Autodesk Fusion 360 part; units mm, degrees
(part 3 of 5)
sketch "草图2 (2)" plane through (0, 0, -0.03) normal (0, 0, 1) x (1, 0, 0) in component "02_模具外套筒"
  line L0 (34, 0) -> (33.9193, 0.5551)
  line L1 (33.9193, 0.5551) -> (33.6891, 1.1029)
  line L2 (33.6891, 1.1029) -> (33.3425, 1.638)
  line L3 (33.3425, 1.638) -> (32.9293, 2.1583)
  line L4 (32.9293, 2.1583) -> (32.5082, 2.6655)
  line L5 (32.5082, 2.6655) -> (32.1374, 3.1653)
  line L6 (32.1374, 3.1653) -> (31.866, 3.6659)
  line L7 (31.866, 3.6659) -> (31.7262, 4.1768)
  line L8 (31.7262, 4.1768) -> (31.7289, 4.7065)
  line L9 (31.7289, 4.7065) -> (31.8616, 5.2604)
  line L10 (31.8616, 5.2604) -> (32.0904, 5.839)
  line L11 (32.0904, 5.839) -> (32.3659, 6.438)
  line L12 (32.3659, 6.438) -> (32.6303, 7.0475)
  line L13 (32.6303, 7.0475) -> (32.8266, 7.6541)
  line L14 (32.8266, 7.6541) -> (32.9072, 8.2428)
  line L15 (32.9072, 8.2428) -> (32.8415, 8.7998)
  line L16 (32.8415, 8.7998) -> (32.6199, 9.3151)
  line L17 (32.6199, 9.3151) -> (32.2557, 9.7847)
  line L18 (32.2557, 9.7847) -> (31.7824, 10.2119)
  line L19 (31.7824, 10.2119) -> (31.2487, 10.6075)
  line L20 (31.2487, 10.6075) -> (30.7106, 10.9884)
  line L21 (30.7106, 10.9884) -> (30.2231, 11.3752)
  line L22 (30.2231, 11.3752) -> (29.8313, 11.7885)
  line L23 (29.8313, 11.7885) -> (29.5641, 12.2459)
  line L24 (29.5641, 12.2459) -> (29.4297, 12.7582)
  line L25 (29.4297, 12.7582) -> (29.4144, 13.3275)
  line L26 (29.4144, 13.3275) -> (29.4857, 13.9457)
  line L27 (29.4857, 13.9457) -> (29.5968, 14.5955)
  line L28 (29.5968, 14.5955) -> (29.6944, 15.2527)
  line L29 (29.6944, 15.2527) -> (29.727, 15.8894)
  line L30 (29.727, 15.8894) -> (29.6525, 16.479)
  line L31 (29.6525, 16.479) -> (29.4449, 17)
  line L32 (29.4449, 17) -> (29.0975, 17.4404)
  line L33 (29.0975, 17.4404) -> (28.6241, 17.7996)
  line L34 (28.6241, 17.7996) -> (28.0564, 18.0898)
  line L35 (28.0564, 18.0898) -> (27.4385, 18.3338)
  line L36 (27.4385, 18.3338) -> (26.8202, 18.5625)
  line L37 (26.8202, 18.5625) -> (26.2492, 18.8099)
  line L38 (26.2492, 18.8099) -> (25.7638, 19.1077)
  line L39 (25.7638, 19.1077) -> (25.3873, 19.4804)
  line L40 (25.3873, 19.4804) -> (25.1248, 19.9405)
  line L41 (25.1248, 19.9405) -> (24.9627, 20.4864)
  line L42 (24.9627, 20.4864) -> (24.8716, 21.102)
  line L43 (24.8716, 21.102) -> (24.8107, 21.7584)
  line L44 (24.8107, 21.7584) -> (24.7349, 22.4184)
  line L45 (24.7349, 22.4184) -> (24.6016, 23.0419)
  line L46 (24.6016, 23.0419) -> (24.3771, 23.5921)
  line L47 (24.3771, 23.5921) -> (24.0416, 24.0416)
  line L48 (24.0416, 24.0416) -> (23.5921, 24.3771)
  line L49 (23.5921, 24.3771) -> (23.0419, 24.6016)
  line L50 (23.0419, 24.6016) -> (22.4184, 24.7349)
  line L51 (22.4184, 24.7349) -> (21.7584, 24.8107)
  line L52 (21.7584, 24.8107) -> (21.102, 24.8716)
  line L53 (21.102, 24.8716) -> (20.4864, 24.9627)
  line L54 (20.4864, 24.9627) -> (19.9405, 25.1248)
  line L55 (19.9405, 25.1248) -> (19.4804, 25.3873)
  line L56 (19.4804, 25.3873) -> (19.1077, 25.7638)
  line L57 (19.1077, 25.7638) -> (18.8099, 26.2492)
  line L58 (18.8099, 26.2492) -> (18.5625, 26.8202)
  line L59 (18.5625, 26.8202) -> (18.3338, 27.4385)
  line L60 (18.3338, 27.4385) -> (18.0898, 28.0564)
  line L61 (18.0898, 28.0564) -> (17.7996, 28.6241)
  line L62 (17.7996, 28.6241) -> (17.4404, 29.0975)
  line L63 (17.4404, 29.0975) -> (17, 29.4449)
  line L64 (17, 29.4449) -> (16.479, 29.6525)
  line L65 (16.479, 29.6525) -> (15.8894, 29.727)
  line L66 (15.8894, 29.727) -> (15.2527, 29.6944)
  line L67 (15.2527, 29.6944) -> (14.5955, 29.5968)
  line L68 (14.5955, 29.5968) -> (13.9457, 29.4857)
  line L69 (13.9457, 29.4857) -> (13.3275, 29.4144)
  line L70 (13.3275, 29.4144) -> (12.7582, 29.4297)
  line L71 (12.7582, 29.4297) -> (12.2459, 29.5641)
  line L72 (12.2459, 29.5641) -> (11.7885, 29.8313)
  line L73 (11.7885, 29.8313) -> (11.3752, 30.2231)
  line L74 (11.3752, 30.2231) -> (10.9884, 30.7106)
  line L75 (10.9884, 30.7106) -> (10.6075, 31.2487)
  line L76 (10.6075, 31.2487) -> (10.2119, 31.7824)
  line L77 (10.2119, 31.7824) -> (9.7847, 32.2557)
  line L78 (9.7847, 32.2557) -> (9.3151, 32.6199)
  line L79 (9.3151, 32.6199) -> (8.7998, 32.8415)
  line L80 (8.7998, 32.8415) -> (8.2428, 32.9072)
  line L81 (8.2428, 32.9072) -> (7.6541, 32.8266)
  line L82 (7.6541, 32.8266) -> (7.0475, 32.6303)
  line L83 (7.0475, 32.6303) -> (6.438, 32.3659)
  line L84 (6.438, 32.3659) -> (5.839, 32.0904)
  line L85 (5.839, 32.0904) -> (5.2604, 31.8616)
  line L86 (5.2604, 31.8616) -> (4.7065, 31.7289)
  line L87 (4.7065, 31.7289) -> (4.1768, 31.7262)
  line L88 (4.1768, 31.7262) -> (3.6659, 31.866)
  line L89 (3.6659, 31.866) -> (3.1653, 32.1374)
  line L90 (3.1653, 32.1374) -> (2.6655, 32.5082)
  line L91 (2.6655, 32.5082) -> (2.1583, 32.9293)
  line L92 (2.1583, 32.9293) -> (1.638, 33.3425)
  line L93 (1.638, 33.3425) -> (1.1029, 33.6891)
  line L94 (1.1029, 33.6891) -> (0.5551, 33.9193)
  line L95 (0.5551, 33.9193) -> (0, 34)
  line L96 (0, 34) -> (-0.5551, 33.9193)
  line L97 (-0.5551, 33.9193) -> (-1.1029, 33.6891)
  line L98 (-1.1029, 33.6891) -> (-1.638, 33.3425)
  line L99 (-1.638, 33.3425) -> (-2.1583, 32.9293)
  line L100 (-2.1583, 32.9293) -> (-2.6655, 32.5082)
  line L101 (-2.6655, 32.5082) -> (-3.1653, 32.1374)
  line L102 (-3.1653, 32.1374) -> (-3.6659, 31.866)
  line L103 (-3.6659, 31.866) -> (-4.1768, 31.7262)
  line L104 (-4.1768, 31.7262) -> (-4.7065, 31.7289)
  line L105 (-4.7065, 31.7289) -> (-5.2604, 31.8616)
  line L106 (-5.2604, 31.8616) -> (-5.839, 32.0904)
  line L107 (-5.839, 32.0904) -> (-6.438, 32.3659)
  line L108 (-6.438, 32.3659) -> (-7.0475, 32.6303)
  line L109 (-7.0475, 32.6303) -> (-7.6541, 32.8266)
  line L110 (-7.6541, 32.8266) -> (-8.2428, 32.9072)
  line L111 (-8.2428, 32.9072) -> (-8.7998, 32.8415)
  line L112 (-8.7998, 32.8415) -> (-9.3151, 32.6199)
  line L113 (-9.3151, 32.6199) -> (-9.7847, 32.2557)
  line L114 (-9.7847, 32.2557) -> (-10.2119, 31.7824)
  line L115 (-10.2119, 31.7824) -> (-10.6075, 31.2487)
  line L116 (-10.6075, 31.2487) -> (-10.9884, 30.7106)
  line L117 (-10.9884, 30.7106) -> (-11.3752, 30.2231)
  line L118 (-11.3752, 30.2231) -> (-11.7885, 29.8313)
  line L119 (-11.7885, 29.8313) -> (-12.2459, 29.5641)
  line L120 (-12.2459, 29.5641) -> (-12.7582, 29.4297)
  line L121 (-12.7582, 29.4297) -> (-13.3275, 29.4144)
  line L122 (-13.3275, 29.4144) -> (-13.9457, 29.4857)
  line L123 (-13.9457, 29.4857) -> (-14.5955, 29.5968)
  line L124 (-14.5955, 29.5968) -> (-15.2527, 29.6944)
  line L125 (-15.2527, 29.6944) -> (-15.8894, 29.727)
  line L126 (-15.8894, 29.727) -> (-16.479, 29.6525)
  line L127 (-16.479, 29.6525) -> (-17, 29.4449)
  line L128 (-17, 29.4449) -> (-17.4404, 29.0975)
  line L129 (-17.4404, 29.0975) -> (-17.7996, 28.6241)
  line L130 (-17.7996, 28.6241) -> (-18.0898, 28.0564)
  line L131 (-18.0898, 28.0564) -> (-18.3338, 27.4385)
  line L132 (-18.3338, 27.4385) -> (-18.5625, 26.8202)
  line L133 (-18.5625, 26.8202) -> (-18.8099, 26.2492)
  line L134 (-18.8099, 26.2492) -> (-19.1077, 25.7638)
  line L135 (-19.1077, 25.7638) -> (-19.4804, 25.3873)
  line L136 (-19.4804, 25.3873) -> (-19.9405, 25.1248)
  line L137 (-19.9405, 25.1248) -> (-20.4864, 24.9627)
  line L138 (-20.4864, 24.9627) -> (-21.102, 24.8716)
  line L139 (-21.102, 24.8716) -> (-21.7584, 24.8107)
  line L140 (-21.7584, 24.8107) -> (-22.4184, 24.7349)
  line L141 (-22.4184, 24.7349) -> (-23.0419, 24.6016)
  line L142 (-23.0419, 24.6016) -> (-23.5921, 24.3771)
  line L143 (-23.5921, 24.3771) -> (-24.0416, 24.0416)
  line L144 (-24.0416, 24.0416) -> (-24.3771, 23.5921)
  line L145 (-24.3771, 23.5921) -> (-24.6016, 23.0419)
  line L146 (-24.6016, 23.0419) -> (-24.7349, 22.4184)
  line L147 (-24.7349, 22.4184) -> (-24.8107, 21.7584)
  line L148 (-24.8107, 21.7584) -> (-24.8716, 21.102)
  line L149 (-24.8716, 21.102) -> (-24.9627, 20.4864)
  line L150 (-24.9627, 20.4864) -> (-25.1248, 19.9405)
  line L151 (-25.1248, 19.9405) -> (-25.3873, 19.4804)
  line L152 (-25.3873, 19.4804) -> (-25.7638, 19.1077)
  line L153 (-25.7638, 19.1077) -> (-26.2492, 18.8099)
  line L154 (-26.2492, 18.8099) -> (-26.8202, 18.5625)
  line L155 (-26.8202, 18.5625) -> (-27.4385, 18.3338)
  line L156 (-27.4385, 18.3338) -> (-28.0564, 18.0898)
  line L157 (-28.0564, 18.0898) -> (-28.6241, 17.7996)
  line L158 (-28.6241, 17.7996) -> (-29.0975, 17.4404)
  line L159 (-29.0975, 17.4404) -> (-29.4449, 17)
  line L160 (-29.4449, 17) -> (-29.6525, 16.479)
  line L161 (-29.6525, 16.479) -> (-29.727, 15.8894)
  line L162 (-29.727, 15.8894) -> (-29.6944, 15.2527)
  line L163 (-29.6944, 15.2527) -> (-29.5968, 14.5955)
  line L164 (-29.5968, 14.5955) -> (-29.4857, 13.9457)
  line L165 (-29.4857, 13.9457) -> (-29.4144, 13.3275)
  line L166 (-29.4144, 13.3275) -> (-29.4297, 12.7582)
  line L167 (-29.4297, 12.7582) -> (-29.5641, 12.2459)
  line L168 (-29.5641, 12.2459) -> (-29.8313, 11.7885)
  line L169 (-29.8313, 11.7885) -> (-30.2231, 11.3752)
  line L170 (-30.2231, 11.3752) -> (-30.7106, 10.9884)
  line L171 (-30.7106, 10.9884) -> (-31.2487, 10.6075)
  line L172 (-31.2487, 10.6075) -> (-31.7824, 10.2119)
  line L173 (-31.7824, 10.2119) -> (-32.2557, 9.7847)
  line L174 (-32.2557, 9.7847) -> (-32.6199, 9.3151)
  line L175 (-32.6199, 9.3151) -> (-32.8415, 8.7998)
  line L176 (-32.8415, 8.7998) -> (-32.9072, 8.2428)
  line L177 (-32.9072, 8.2428) -> (-32.8266, 7.6541)
  line L178 (-32.8266, 7.6541) -> (-32.6303, 7.0475)
  line L179 (-32.6303, 7.0475) -> (-32.3659, 6.438)
  line L180 (-32.3659, 6.438) -> (-32.0904, 5.839)
  line L181 (-32.0904, 5.839) -> (-31.8616, 5.2604)
  line L182 (-31.8616, 5.2604) -> (-31.7289, 4.7065)
  line L183 (-31.7289, 4.7065) -> (-31.7262, 4.1768)
  line L184 (-31.7262, 4.1768) -> (-31.866, 3.6659)
  line L185 (-31.866, 3.6659) -> (-32.1374, 3.1653)
  line L186 (-32.1374, 3.1653) -> (-32.5082, 2.6655)
  line L187 (-32.5082, 2.6655) -> (-32.9293, 2.1583)
  line L188 (-32.9293, 2.1583) -> (-33.3425, 1.638)
  line L189 (-33.3425, 1.638) -> (-33.6891, 1.1029)
  line L190 (-33.6891, 1.1029) -> (-33.9193, 0.5551)
  line L191 (-33.9193, 0.5551) -> (-34, 0)
  line L192 (-34, 0) -> (-33.9193, -0.5551)
  line L193 (-33.9193, -0.5551) -> (-33.6891, -1.1029)
  line L194 (-33.6891, -1.1029) -> (-33.3425, -1.638)
  line L195 (-33.3425, -1.638) -> (-32.9293, -2.1583)
  line L196 (-32.9293, -2.1583) -> (-32.5082, -2.6655)
  line L197 (-32.5082, -2.6655) -> (-32.1374, -3.1653)
  line L198 (-32.1374, -3.1653) -> (-31.866, -3.6659)
  line L199 (-31.866, -3.6659) -> (-31.7262, -4.1768)
  line L200 (-31.7262, -4.1768) -> (-31.7289, -4.7065)
  line L201 (-31.7289, -4.7065) -> (-31.8616, -5.2604)
  line L202 (-31.8616, -5.2604) -> (-32.0904, -5.839)
  line L203 (-32.0904, -5.839) -> (-32.3659, -6.438)
  line L204 (-32.3659, -6.438) -> (-32.6303, -7.0475)
  line L205 (-32.6303, -7.0475) -> (-32.8266, -7.6541)
  line L206 (-32.8266, -7.6541) -> (-32.9072, -8.2428)
  line L207 (-32.9072, -8.2428) -> (-32.8415, -8.7998)
  line L208 (-32.8415, -8.7998) -> (-32.6199, -9.3151)
  line L209 (-32.6199, -9.3151) -> (-32.2557, -9.7847)
  line L210 (-32.2557, -9.7847) -> (-31.7824, -10.2119)
  line L211 (-31.7824, -10.2119) -> (-31.2487, -10.6075)
  line L212 (-31.2487, -10.6075) -> (-30.7106, -10.9884)
  line L213 (-30.7106, -10.9884) -> (-30.2231, -11.3752)
  line L214 (-30.2231, -11.3752) -> (-29.8313, -11.7885)
  line L215 (-29.8313, -11.7885) -> (-29.5641, -12.2459)
  line L216 (-29.5641, -12.2459) -> (-29.4297, -12.7582)
  line L217 (-29.4297, -12.7582) -> (-29.4144, -13.3275)
  line L218 (-29.4144, -13.3275) -> (-29.4857, -13.9457)
  line L219 (-29.4857, -13.9457) -> (-29.5968, -14.5955)
  line L220 (-29.5968, -14.5955) -> (-29.6944, -15.2527)
  line L221 (-29.6944, -15.2527) -> (-29.727, -15.8894)
  line L222 (-29.727, -15.8894) -> (-29.6525, -16.479)
  line L223 (-29.6525, -16.479) -> (-29.4449, -17)
  line L224 (-29.4449, -17) -> (-29.0975, -17.4404)
  line L225 (-29.0975, -17.4404) -> (-28.6241, -17.7996)
  line L226 (-28.6241, -17.7996) -> (-28.0564, -18.0898)
  line L227 (-28.0564, -18.0898) -> (-27.4385, -18.3338)
  line L228 (-27.4385, -18.3338) -> (-26.8202, -18.5625)
  line L229 (-26.8202, -18.5625) -> (-26.2492, -18.8099)
  line L230 (-26.2492, -18.8099) -> (-25.7638, -19.1077)
  line L231 (-25.7638, -19.1077) -> (-25.3873, -19.4804)
  line L232 (-25.3873, -19.4804) -> (-25.1248, -19.9405)
  line L233 (-25.1248, -19.9405) -> (-24.9627, -20.4864)
  line L234 (-24.9627, -20.4864) -> (-24.8716, -21.102)
  line L235 (-24.8716, -21.102) -> (-24.8107, -21.7584)
  line L236 (-24.8107, -21.7584) -> (-24.7349, -22.4184)
  line L237 (-24.7349, -22.4184) -> (-24.6016, -23.0419)
  line L238 (-24.6016, -23.0419) -> (-24.3771, -23.5921)
  line L239 (-24.3771, -23.5921) -> (-24.0416, -24.0416)
  line L240 (-24.0416, -24.0416) -> (-23.5921, -24.3771)
  line L241 (-23.5921, -24.3771) -> (-23.0419, -24.6016)
  line L242 (-23.0419, -24.6016) -> (-22.4184, -24.7349)
  line L243 (-22.4184, -24.7349) -> (-21.7584, -24.8107)
  line L244 (-21.7584, -24.8107) -> (-21.102, -24.8716)
  line L245 (-21.102, -24.8716) -> (-20.4864, -24.9627)
  line L246 (-20.4864, -24.9627) -> (-19.9405, -25.1248)
  line L247 (-19.9405, -25.1248) -> (-19.4804, -25.3873)
  line L248 (-19.4804, -25.3873) -> (-19.1077, -25.7638)
  line L249 (-19.1077, -25.7638) -> (-18.8099, -26.2492)
  line L250 (-18.8099, -26.2492) -> (-18.5625, -26.8202)
  line L251 (-18.5625, -26.8202) -> (-18.3338, -27.4385)
  line L252 (-18.3338, -27.4385) -> (-18.0898, -28.0564)
  line L253 (-18.0898, -28.0564) -> (-17.7996, -28.6241)
  line L254 (-17.7996, -28.6241) -> (-17.4404, -29.0975)
  line L255 (-17.4404, -29.0975) -> (-17, -29.4449)
  line L256 (-17, -29.4449) -> (-16.479, -29.6525)
  line L257 (-16.479, -29.6525) -> (-15.8894, -29.727)
  line L258 (-15.8894, -29.727) -> (-15.2527, -29.6944)
  line L259 (-15.2527, -29.6944) -> (-14.5955, -29.5968)
  line L260 (-14.5955, -29.5968) -> (-13.9457, -29.4857)
  line L261 (-13.9457, -29.4857) -> (-13.3275, -29.4144)
  line L262 (-13.3275, -29.4144) -> (-12.7582, -29.4297)
  line L263 (-12.7582, -29.4297) -> (-12.2459, -29.5641)
  line L264 (-12.2459, -29.5641) -> (-11.7885, -29.8313)
  line L265 (-11.7885, -29.8313) -> (-11.3752, -30.2231)
  line L266 (-11.3752, -30.2231) -> (-10.9884, -30.7106)
  line L267 (-10.9884, -30.7106) -> (-10.6075, -31.2487)
  line L268 (-10.6075, -31.2487) -> (-10.2119, -31.7824)
  line L269 (-10.2119, -31.7824) -> (-9.7847, -32.2557)
  line L270 (-9.7847, -32.2557) -> (-9.3151, -32.6199)
  line L271 (-9.3151, -32.6199) -> (-8.7998, -32.8415)
  line L272 (-8.7998, -32.8415) -> (-8.2428, -32.9072)
  line L273 (-8.2428, -32.9072) -> (-7.6541, -32.8266)
  line L274 (-7.6541, -32.8266) -> (-7.0475, -32.6303)
  line L275 (-7.0475, -32.6303) -> (-6.438, -32.3659)
  line L276 (-6.438, -32.3659) -> (-5.839, -32.0904)
  line L277 (-5.839, -32.0904) -> (-5.2604, -31.8616)
  line L278 (-5.2604, -31.8616) -> (-4.7065, -31.7289)
  line L279 (-4.7065, -31.7289) -> (-4.1768, -31.7262)
  line L280 (-4.1768, -31.7262) -> (-3.6659, -31.866)
  line L281 (-3.6659, -31.866) -> (-3.1653, -32.1374)
  line L282 (-3.1653, -32.1374) -> (-2.6655, -32.5082)
  line L283 (-2.6655, -32.5082) -> (-2.1583, -32.9293)
  line L284 (-2.1583, -32.9293) -> (-1.638, -33.3425)
  line L285 (-1.638, -33.3425) -> (-1.1029, -33.6891)
  line L286 (-1.1029, -33.6891) -> (-0.5551, -33.9193)
  line L287 (-0.5551, -33.9193) -> (0, -34)
  line L288 (0, -34) -> (0.5551, -33.9193)
  line L289 (0.5551, -33.9193) -> (1.1029, -33.6891)
  line L290 (1.1029, -33.6891) -> (1.638, -33.3425)
  line L291 (1.638, -33.3425) -> (2.1583, -32.9293)
  line L292 (2.1583, -32.9293) -> (2.6655, -32.5082)
  line L293 (2.6655, -32.5082) -> (3.1653, -32.1374)
  line L294 (3.1653, -32.1374) -> (3.6659, -31.866)
  line L295 (3.6659, -31.866) -> (4.1768, -31.7262)
  line L296 (4.1768, -31.7262) -> (4.7065, -31.7289)
  line L297 (4.7065, -31.7289) -> (5.2604, -31.8616)
  line L298 (5.2604, -31.8616) -> (5.839, -32.0904)
  line L299 (5.839, -32.0904) -> (6.438, -32.3659)
  line L300 (6.438, -32.3659) -> (7.0475, -32.6303)
  line L301 (7.0475, -32.6303) -> (7.6541, -32.8266)
  line L302 (7.6541, -32.8266) -> (8.2428, -32.9072)
  line L303 (8.2428, -32.9072) -> (8.7998, -32.8415)
  line L304 (8.7998, -32.8415) -> (9.3151, -32.6199)
  line L305 (9.3151, -32.6199) -> (9.7847, -32.2557)
  line L306 (9.7847, -32.2557) -> (10.2119, -31.7824)
  line L307 (10.2119, -31.7824) -> (10.6075, -31.2487)
  line L308 (10.6075, -31.2487) -> (10.9884, -30.7106)
  line L309 (10.9884, -30.7106) -> (11.3752, -30.2231)
  line L310 (11.3752, -30.2231) -> (11.7885, -29.8313)
  line L311 (11.7885, -29.8313) -> (12.2459, -29.5641)
  line L312 (12.2459, -29.5641) -> (12.7582, -29.4297)
  line L313 (12.7582, -29.4297) -> (13.3275, -29.4144)
  line L314 (13.3275, -29.4144) -> (13.9457, -29.4857)
  line L315 (13.9457, -29.4857) -> (14.5955, -29.5968)
  line L316 (14.5955, -29.5968) -> (15.2527, -29.6944)
  line L317 (15.2527, -29.6944) -> (15.8894, -29.727)
  line L318 (15.8894, -29.727) -> (16.479, -29.6525)
  line L319 (16.479, -29.6525) -> (17, -29.4449)
  line L320 (17, -29.4449) -> (17.4404, -29.0975)
  line L321 (17.4404, -29.0975) -> (17.7996, -28.6241)
  line L322 (17.7996, -28.6241) -> (18.0898, -28.0564)
  line L323 (18.0898, -28.0564) -> (18.3338, -27.4385)
  line L324 (18.3338, -27.4385) -> (18.5625, -26.8202)
  line L325 (18.5625, -26.8202) -> (18.8099, -26.2492)
  line L326 (18.8099, -26.2492) -> (19.1077, -25.7638)
  line L327 (19.1077, -25.7638) -> (19.4804, -25.3873)
  line L328 (19.4804, -25.3873) -> (19.9405, -25.1248)
  line L329 (19.9405, -25.1248) -> (20.4864, -24.9627)
  line L330 (20.4864, -24.9627) -> (21.102, -24.8716)
  line L331 (21.102, -24.8716) -> (21.7584, -24.8107)
  line L332 (21.7584, -24.8107) -> (22.4184, -24.7349)
  line L333 (22.4184, -24.7349) -> (23.0419, -24.6016)
  line L334 (23.0419, -24.6016) -> (23.5921, -24.3771)
  line L335 (23.5921, -24.3771) -> (24.0416, -24.0416)
  line L336 (24.0416, -24.0416) -> (24.3771, -23.5921)
  line L337 (24.3771, -23.5921) -> (24.6016, -23.0419)
  line L338 (24.6016, -23.0419) -> (24.7349, -22.4184)
  line L339 (24.7349, -22.4184) -> (24.8107, -21.7584)
  line L340 (24.8107, -21.7584) -> (24.8716, -21.102)
  line L341 (24.8716, -21.102) -> (24.9627, -20.4864)
  line L342 (24.9627, -20.4864) -> (25.1248, -19.9405)
  line L343 (25.1248, -19.9405) -> (25.3873, -19.4804)
  line L344 (25.3873, -19.4804) -> (25.7638, -19.1077)
  line L345 (25.7638, -19.1077) -> (26.2492, -18.8099)
  line L346 (26.2492, -18.8099) -> (26.8202, -18.5625)
  line L347 (26.8202, -18.5625) -> (27.4385, -18.3338)
  line L348 (27.4385, -18.3338) -> (28.0564, -18.0898)
  line L349 (28.0564, -18.0898) -> (28.6241, -17.7996)
  line L350 (28.6241, -17.7996) -> (29.0975, -17.4404)
  line L351 (29.0975, -17.4404) -> (29.4449, -17)
  line L352 (29.4449, -17) -> (29.6525, -16.479)
  line L353 (29.6525, -16.479) -> (29.727, -15.8894)
  line L354 (29.727, -15.8894) -> (29.6944, -15.2527)
  line L355 (29.6944, -15.2527) -> (29.5968, -14.5955)
  line L356 (29.5968, -14.5955) -> (29.4857, -13.9457)
  line L357 (29.4857, -13.9457) -> (29.4144, -13.3275)
  line L358 (29.4144, -13.3275) -> (29.4297, -12.7582)
  line L359 (29.4297, -12.7582) -> (29.5641, -12.2459)
  line L360 (29.5641, -12.2459) -> (29.8313, -11.7885)
  line L361 (29.8313, -11.7885) -> (30.2231, -11.3752)
  line L362 (30.2231, -11.3752) -> (30.7106, -10.9884)
  line L363 (30.7106, -10.9884) -> (31.2487, -10.6075)
  line L364 (31.2487, -10.6075) -> (31.7824, -10.2119)
  line L365 (31.7824, -10.2119) -> (32.2557, -9.7847)
  line L366 (32.2557, -9.7847) -> (32.6199, -9.3151)
  line L367 (32.6199, -9.3151) -> (32.8415, -8.7998)
  line L368 (32.8415, -8.7998) -> (32.9072, -8.2428)
  line L369 (32.9072, -8.2428) -> (32.8266, -7.6541)
  line L370 (32.8266, -7.6541) -> (32.6303, -7.0475)
  line L371 (32.6303, -7.0475) -> (32.3659, -6.438)
  line L372 (32.3659, -6.438) -> (32.0904, -5.839)
  line L373 (32.0904, -5.839) -> (31.8616, -5.2604)
  line L374 (31.8616, -5.2604) -> (31.7289, -4.7065)
  line L375 (31.7289, -4.7065) -> (31.7262, -4.1768)
  line L376 (31.7262, -4.1768) -> (31.866, -3.6659)
  line L377 (31.866, -3.6659) -> (32.1374, -3.1653)
  line L378 (32.1374, -3.1653) -> (32.5082, -2.6655)
  line L379 (32.5082, -2.6655) -> (32.9293, -2.1583)
  line L380 (32.9293, -2.1583) -> (33.3425, -1.638)
  line L381 (33.3425, -1.638) -> (33.6891, -1.1029)
  line L382 (33.6891, -1.1029) -> (33.9193, -0.5551)
  line L383 (33.9193, -0.5551) -> (34, 0)
extrude "配合花边内腔 (1)" cut sketch "草图2 (2)" along normal blind 50.06 bodies 2 in component "02_模具外套筒"
ref_plane "工作平面2" through (0, 0, 49.97) normal (0, 0, 1) x (1, 0, 0) in component "02_模具外套筒"
sketch "草图3 (2)" plane through (0, 0, 49.97) normal (0, 0, 1) x (1, 0, 0) in component "02_模具外套筒"
  circle A0 centre (0, 0) radius 37.5
  circle A1 centre (0, 0) radius 6.3
extrude "推杆导向顶盖 (1)" add sketch "草图3 (2)" along normal blind 3.53 bodies 2 in component "02_模具外套筒"
ref_plane "工作平面3" through (0, 0, 42) normal (0, 0, 1) x (1, 0, 0) in component "02_模具外套筒"
sketch "草图4 (2)" plane through (0, 0, 42) normal (0, 0, 1) x (1, 0, 0) in component "02_模具外套筒"
  line L0 (-53.5, -9) -> (-35.5, -9)
  line L1 (-35.5, -9) -> (-35.5, 9)
  line L2 (-35.5, 9) -> (-53.5, 9)
  line L3 (-53.5, 9) -> (-53.5, -9)
extrude "套筒握耳 (1)" add sketch "草图4 (2)" along normal blind 6 bodies 2 in component "02_模具外套筒"
ref_plane "工作平面4" through (0, 0, 42) normal (0, 0, 1) x (1, 0, 0) in component "02_模具外套筒"
sketch "草图5 (2)" plane through (0, 0, 42) normal (0, 0, 1) x (1, 0, 0) in component "02_模具外套筒"
  line L0 (35.5, -9) -> (53.5, -9)
  line L1 (53.5, -9) -> (53.5, 9)
  line L2 (53.5, 9) -> (35.5, 9)
  line L3 (35.5, 9) -> (35.5, -9)
extrude "套筒握耳 (2)" add sketch "草图5 (2)" along normal blind 6 bodies 2 in component "02_模具外套筒"
sketch "草图1 (3)" plane through (0, 0, 0) normal (0, 0, 1) x (1, 0, 0) in component "03_可换镜像凹纹压片"
  line L0 (-33.6193, -0.5502) -> (-33.3893, -1.0931)
  line L1 (-33.3893, -1.0931) -> (-33.0429, -1.6233)
  line L2 (-33.0429, -1.6233) -> (-32.6299, -2.1387)
  line L3 (-32.6299, -2.1387) -> (-32.2092, -2.641)
  line L4 (-32.2092, -2.641) -> (-31.8388, -3.1359)
  line L5 (-31.8388, -3.1359) -> (-31.568, -3.6316)
  line L6 (-31.568, -3.6316) -> (-31.4288, -4.1376)
  line L7 (-31.4288, -4.1376) -> (-31.4321, -4.6625)
  line L8 (-31.4321, -4.6625) -> (-31.5656, -5.2115)
  line L9 (-31.5656, -5.2115) -> (-31.7952, -5.7853)
  line L10 (-31.7952, -5.7853) -> (-32.0717, -6.3795)
  line L11 (-32.0717, -6.3795) -> (-32.3371, -6.9842)
  line L12 (-32.3371, -6.9842) -> (-32.5344, -7.586)
  line L13 (-32.5344, -7.586) -> (-32.6162, -8.1699)
  line L14 (-32.6162, -8.1699) -> (-32.5517, -8.7222)
  line L15 (-32.5517, -8.7222) -> (-32.3314, -9.2327)
  line L16 (-32.3314, -9.2327) -> (-31.9686, -9.6976)
  line L17 (-31.9686, -9.6976) -> (-31.4968, -10.1201)
  line L18 (-31.4968, -10.1201) -> (-30.9646, -10.5111)
  line L19 (-30.9646, -10.5111) -> (-30.4281, -10.8873)
  line L20 (-30.4281, -10.8873) -> (-29.9423, -11.2695)
  line L21 (-29.9423, -11.2695) -> (-29.5523, -11.6782)
  line L22 (-29.5523, -11.6782) -> (-29.2869, -12.1311)
  line L23 (-29.2869, -12.1311) -> (-29.1545, -12.6389)
  line L24 (-29.1545, -12.6389) -> (-29.1411, -13.2037)
  line L25 (-29.1411, -13.2037) -> (-29.2145, -13.8174)
  line L26 (-29.2145, -13.8174) -> (-29.3277, -14.4628)
  line L27 (-29.3277, -14.4628) -> (-29.4275, -15.1156)
  line L28 (-29.4275, -15.1156) -> (-29.4624, -15.748)
  line L29 (-29.4624, -15.748) -> (-29.3903, -16.3333)
  line L30 (-29.3903, -16.3333) -> (-29.1851, -16.85)
  line L31 (-29.1851, -16.85) -> (-28.8402, -17.2862)
  line L32 (-28.8402, -17.2862) -> (-28.3693, -17.6412)
  line L33 (-28.3693, -17.6412) -> (-27.8043, -17.9272)
  line L34 (-27.8043, -17.9272) -> (-27.1891, -18.1671)
  line L35 (-27.1891, -18.1671) -> (-26.5735, -18.3918)
  line L36 (-26.5735, -18.3918) -> (-26.0053, -18.6352)
  line L37 (-26.0053, -18.6352) -> (-25.5228, -18.929)
  line L38 (-25.5228, -18.929) -> (-25.1493, -19.2978)
  line L39 (-25.1493, -19.2978) -> (-24.8898, -19.754)
  line L40 (-24.8898, -19.754) -> (-24.7308, -20.2961)
  line L41 (-24.7308, -20.2961) -> (-24.6428, -20.9079)
  line L42 (-24.6428, -20.9079) -> (-24.5851, -21.5606)
  line L43 (-24.5851, -21.5606) -> (-24.5126, -22.2169)
  line L44 (-24.5126, -22.2169) -> (-24.3826, -22.8368)
  line L45 (-24.3826, -22.8368) -> (-24.1615, -23.3835)
  line L46 (-24.1615, -23.3835) -> (-23.8295, -23.8295)
  line L47 (-23.8295, -23.8295) -> (-23.3835, -24.1615)
  line L48 (-23.3835, -24.1615) -> (-22.8368, -24.3826)
  line L49 (-22.8368, -24.3826) -> (-22.2169, -24.5126)
  line L50 (-22.2169, -24.5126) -> (-21.5606, -24.5851)
  line L51 (-21.5606, -24.5851) -> (-20.9079, -24.6428)
  line L52 (-20.9079, -24.6428) -> (-20.2961, -24.7308)
  line L53 (-20.2961, -24.7308) -> (-19.754, -24.8898)
  line L54 (-19.754, -24.8898) -> (-19.2978, -25.1493)
  line L55 (-19.2978, -25.1493) -> (-18.929, -25.5228)
  line L56 (-18.929, -25.5228) -> (-18.6352, -26.0053)
  line L57 (-18.6352, -26.0053) -> (-18.3918, -26.5735)
  line L58 (-18.3918, -26.5735) -> (-18.1671, -27.1891)
  line L59 (-18.1671, -27.1891) -> (-17.9272, -27.8043)
  line L60 (-17.9272, -27.8043) -> (-17.6412, -28.3693)
  line L61 (-17.6412, -28.3693) -> (-17.2862, -28.8402)
  line L62 (-17.2862, -28.8402) -> (-16.85, -29.1851)
  line L63 (-16.85, -29.1851) -> (-16.3333, -29.3903)
  line L64 (-16.3333, -29.3903) -> (-15.748, -29.4624)
  line L65 (-15.748, -29.4624) -> (-15.1156, -29.4275)
  line L66 (-15.1156, -29.4275) -> (-14.4628, -29.3277)
  line L67 (-14.4628, -29.3277) -> (-13.8174, -29.2145)
  line L68 (-13.8174, -29.2145) -> (-13.2037, -29.1411)
  line L69 (-13.2037, -29.1411) -> (-12.6389, -29.1545)
  line L70 (-12.6389, -29.1545) -> (-12.1311, -29.2869)
  line L71 (-12.1311, -29.2869) -> (-11.6782, -29.5523)
  line L72 (-11.6782, -29.5523) -> (-11.2695, -29.9423)
  line L73 (-11.2695, -29.9423) -> (-10.8873, -30.4281)
  line L74 (-10.8873, -30.4281) -> (-10.5111, -30.9646)
  line L75 (-10.5111, -30.9646) -> (-10.1201, -31.4968)
  line L76 (-10.1201, -31.4968) -> (-9.6976, -31.9686)
  line L77 (-9.6976, -31.9686) -> (-9.2327, -32.3314)
  line L78 (-9.2327, -32.3314) -> (-8.7222, -32.5517)
  line L79 (-8.7222, -32.5517) -> (-8.1699, -32.6162)
  line L80 (-8.1699, -32.6162) -> (-7.586, -32.5344)
  line L81 (-7.586, -32.5344) -> (-6.9842, -32.3371)
  line L82 (-6.9842, -32.3371) -> (-6.3795, -32.0717)
  line L83 (-6.3795, -32.0717) -> (-5.7853, -31.7952)
  line L84 (-5.7853, -31.7952) -> (-5.2115, -31.5656)
  line L85 (-5.2115, -31.5656) -> (-4.6625, -31.4321)
  line L86 (-4.6625, -31.4321) -> (-4.1376, -31.4288)
  line L87 (-4.1376, -31.4288) -> (-3.6316, -31.568)
  line L88 (-3.6316, -31.568) -> (-3.1359, -31.8388)
  line L89 (-3.1359, -31.8388) -> (-2.641, -32.2092)
  line L90 (-2.641, -32.2092) -> (-2.1387, -32.6299)
  line L91 (-2.1387, -32.6299) -> (-1.6233, -33.0429)
  line L92 (-1.6233, -33.0429) -> (-1.0931, -33.3893)
  line L93 (-1.0931, -33.3893) -> (-0.5502, -33.6193)
  line L94 (-0.5502, -33.6193) -> (0, -33.7)
  line L95 (0, -33.7) -> (0.5502, -33.6193)
  line L96 (0.5502, -33.6193) -> (1.0931, -33.3893)
  line L97 (1.0931, -33.3893) -> (1.6233, -33.0429)
  line L98 (1.6233, -33.0429) -> (2.1387, -32.6299)
  line L99 (2.1387, -32.6299) -> (2.641, -32.2092)
  line L100 (2.641, -32.2092) -> (3.1359, -31.8388)
  line L101 (3.1359, -31.8388) -> (3.6316, -31.568)
  line L102 (3.6316, -31.568) -> (4.1376, -31.4288)
  line L103 (4.1376, -31.4288) -> (4.6625, -31.4321)
  line L104 (4.6625, -31.4321) -> (5.2115, -31.5656)
  line L105 (5.2115, -31.5656) -> (5.7853, -31.7952)
  line L106 (5.7853, -31.7952) -> (6.3795, -32.0717)
  line L107 (6.3795, -32.0717) -> (6.9842, -32.3371)
  line L108 (6.9842, -32.3371) -> (7.586, -32.5344)
  line L109 (7.586, -32.5344) -> (8.1699, -32.6162)
  line L110 (8.1699, -32.6162) -> (8.7222, -32.5517)
  line L111 (8.7222, -32.5517) -> (9.2327, -32.3314)
  line L112 (9.2327, -32.3314) -> (9.6976, -31.9686)
  line L113 (9.6976, -31.9686) -> (10.1201, -31.4968)
  line L114 (10.1201, -31.4968) -> (10.5111, -30.9646)
  line L115 (10.5111, -30.9646) -> (10.8873, -30.4281)
  line L116 (10.8873, -30.4281) -> (11.2695, -29.9423)
  line L117 (11.2695, -29.9423) -> (11.6782, -29.5523)
  line L118 (11.6782, -29.5523) -> (12.1311, -29.2869)
  line L119 (12.1311, -29.2869) -> (12.6389, -29.1545)
  line L120 (12.6389, -29.1545) -> (13.2037, -29.1411)
  line L121 (13.2037, -29.1411) -> (13.8174, -29.2145)
  line L122 (13.8174, -29.2145) -> (14.4628, -29.3277)
  line L123 (14.4628, -29.3277) -> (15.1156, -29.4275)
  line L124 (15.1156, -29.4275) -> (15.748, -29.4624)
  line L125 (15.748, -29.4624) -> (16.3333, -29.3903)
  line L126 (16.3333, -29.3903) -> (16.85, -29.1851)
  line L127 (16.85, -29.1851) -> (17.2862, -28.8402)
  line L128 (17.2862, -28.8402) -> (17.6412, -28.3693)
  line L129 (17.6412, -28.3693) -> (17.9272, -27.8043)
  line L130 (17.9272, -27.8043) -> (18.1671, -27.1891)
  line L131 (18.1671, -27.1891) -> (18.3918, -26.5735)
  line L132 (18.3918, -26.5735) -> (18.6352, -26.0053)
  line L133 (18.6352, -26.0053) -> (18.929, -25.5228)
  line L134 (18.929, -25.5228) -> (19.2978, -25.1493)
  line L135 (19.2978, -25.1493) -> (19.754, -24.8898)
  line L136 (19.754, -24.8898) -> (20.2961, -24.7308)
  line L137 (20.2961, -24.7308) -> (20.9079, -24.6428)
  line L138 (20.9079, -24.6428) -> (21.5606, -24.5851)
  line L139 (21.5606, -24.5851) -> (22.2169, -24.5126)
  line L140 (22.2169, -24.5126) -> (22.8368, -24.3826)
  line L141 (22.8368, -24.3826) -> (23.3835, -24.1615)
  line L142 (23.3835, -24.1615) -> (23.8295, -23.8295)
  line L143 (23.8295, -23.8295) -> (24.1615, -23.3835)
  line L144 (24.1615, -23.3835) -> (24.3826, -22.8368)
  line L145 (24.3826, -22.8368) -> (24.5126, -22.2169)
  line L146 (24.5126, -22.2169) -> (24.5851, -21.5606)
  line L147 (24.5851, -21.5606) -> (24.6428, -20.9079)
  line L148 (24.6428, -20.9079) -> (24.7308, -20.2961)
  line L149 (24.7308, -20.2961) -> (24.8898, -19.754)
  line L150 (24.8898, -19.754) -> (25.1493, -19.2978)
  line L151 (25.1493, -19.2978) -> (25.5228, -18.929)
  line L152 (25.5228, -18.929) -> (26.0053, -18.6352)
  line L153 (26.0053, -18.6352) -> (26.5735, -18.3918)
  line L154 (26.5735, -18.3918) -> (27.1891, -18.1671)
  line L155 (27.1891, -18.1671) -> (27.8043, -17.9272)
  line L156 (27.8043, -17.9272) -> (28.3693, -17.6412)
  line L157 (28.3693, -17.6412) -> (28.8402, -17.2862)
  line L158 (28.8402, -17.2862) -> (29.1851, -16.85)
  line L159 (29.1851, -16.85) -> (29.3903, -16.3333)
  line L160 (29.3903, -16.3333) -> (29.4624, -15.748)
  line L161 (29.4624, -15.748) -> (29.4275, -15.1156)
  line L162 (29.4275, -15.1156) -> (29.3277, -14.4628)
  line L163 (29.3277, -14.4628) -> (29.2145, -13.8174)
  line L164 (29.2145, -13.8174) -> (29.1411, -13.2037)
  line L165 (29.1411, -13.2037) -> (29.1545, -12.6389)
  line L166 (29.1545, -12.6389) -> (29.2869, -12.1311)
  line L167 (29.2869, -12.1311) -> (29.5523, -11.6782)
  line L168 (29.5523, -11.6782) -> (29.9423, -11.2695)
  line L169 (29.9423, -11.2695) -> (30.4281, -10.8873)
  line L170 (30.4281, -10.8873) -> (30.9646, -10.5111)
  line L171 (30.9646, -10.5111) -> (31.4968, -10.1201)
  line L172 (31.4968, -10.1201) -> (31.9686, -9.6976)
  line L173 (31.9686, -9.6976) -> (32.3314, -9.2327)
  line L174 (32.3314, -9.2327) -> (32.5517, -8.7222)
  line L175 (32.5517, -8.7222) -> (32.6162, -8.1699)
  line L176 (32.6162, -8.1699) -> (32.5344, -7.586)
  line L177 (32.5344, -7.586) -> (32.3371, -6.9842)
  line L178 (32.3371, -6.9842) -> (32.0717, -6.3795)
  line L179 (32.0717, -6.3795) -> (31.7952, -5.7853)
  line L180 (31.7952, -5.7853) -> (31.5656, -5.2115)
  line L181 (31.5656, -5.2115) -> (31.4321, -4.6625)
  line L182 (31.4321, -4.6625) -> (31.4288, -4.1376)
  line L183 (31.4288, -4.1376) -> (31.568, -3.6316)
  line L184 (31.568, -3.6316) -> (31.8388, -3.1359)
  line L185 (31.8388, -3.1359) -> (32.2092, -2.641)
  line L186 (32.2092, -2.641) -> (32.6299, -2.1387)
  line L187 (32.6299, -2.1387) -> (33.0429, -1.6233)
  line L188 (33.0429, -1.6233) -> (33.3893, -1.0931)
  line L189 (33.3893, -1.0931) -> (33.6193, -0.5502)
  line L190 (33.6193, -0.5502) -> (33.7, 0)
  line L191 (33.7, 0) -> (33.6193, 0.5502)
  line L192 (33.6193, 0.5502) -> (33.3893, 1.0931)
  line L193 (33.3893, 1.0931) -> (33.0429, 1.6233)
  line L194 (33.0429, 1.6233) -> (32.6299, 2.1387)
  line L195 (32.6299, 2.1387) -> (32.2092, 2.641)
  line L196 (32.2092, 2.641) -> (31.8388, 3.1359)
  line L197 (31.8388, 3.1359) -> (31.568, 3.6316)
  line L198 (31.568, 3.6316) -> (31.4288, 4.1376)
  line L199 (31.4288, 4.1376) -> (31.4321, 4.6625)
  line L200 (31.4321, 4.6625) -> (31.5656, 5.2115)
  line L201 (31.5656, 5.2115) -> (31.7952, 5.7853)
  line L202 (31.7952, 5.7853) -> (32.0717, 6.3795)
  line L203 (32.0717, 6.3795) -> (32.3371, 6.9842)
  line L204 (32.3371, 6.9842) -> (32.5344, 7.586)
  line L205 (32.5344, 7.586) -> (32.6162, 8.1699)
  line L206 (32.6162, 8.1699) -> (32.5517, 8.7222)
  line L207 (32.5517, 8.7222) -> (32.3314, 9.2327)
  line L208 (32.3314, 9.2327) -> (31.9686, 9.6976)
  line L209 (31.9686, 9.6976) -> (31.4968, 10.1201)
  line L210 (31.4968, 10.1201) -> (30.9646, 10.5111)
  line L211 (30.9646, 10.5111) -> (30.4281, 10.8873)
  line L212 (30.4281, 10.8873) -> (29.9423, 11.2695)
  line L213 (29.9423, 11.2695) -> (29.5523, 11.6782)
  line L214 (29.5523, 11.6782) -> (29.2869, 12.1311)
  line L215 (29.2869, 12.1311) -> (29.1545, 12.6389)
  line L216 (29.1545, 12.6389) -> (29.1411, 13.2037)
  line L217 (29.1411, 13.2037) -> (29.2145, 13.8174)
  line L218 (29.2145, 13.8174) -> (29.3277, 14.4628)
  line L219 (29.3277, 14.4628) -> (29.4275, 15.1156)
  line L220 (29.4275, 15.1156) -> (29.4624, 15.748)
  line L221 (29.4624, 15.748) -> (29.3903, 16.3333)
  line L222 (29.3903, 16.3333) -> (29.1851, 16.85)
  line L223 (29.1851, 16.85) -> (28.8402, 17.2862)
  line L224 (28.8402, 17.2862) -> (28.3693, 17.6412)
  line L225 (28.3693, 17.6412) -> (27.8043, 17.9272)
  line L226 (27.8043, 17.9272) -> (27.1891, 18.1671)
  line L227 (27.1891, 18.1671) -> (26.5735, 18.3918)
  line L228 (26.5735, 18.3918) -> (26.0053, 18.6352)
  line L229 (26.0053, 18.6352) -> (25.5228, 18.929)
  line L230 (25.5228, 18.929) -> (25.1493, 19.2978)
  line L231 (25.1493, 19.2978) -> (24.8898, 19.754)
  line L232 (24.8898, 19.754) -> (24.7308, 20.2961)
  line L233 (24.7308, 20.2961) -> (24.6428, 20.9079)
  line L234 (24.6428, 20.9079) -> (24.5851, 21.5606)
  line L235 (24.5851, 21.5606) -> (24.5126, 22.2169)
  line L236 (24.5126, 22.2169) -> (24.3826, 22.8368)
  line L237 (24.3826, 22.8368) -> (24.1615, 23.3835)
  line L238 (24.1615, 23.3835) -> (23.8295, 23.8295)
  line L239 (23.8295, 23.8295) -> (23.3835, 24.1615)
  line L240 (23.3835, 24.1615) -> (22.8368, 24.3826)
  line L241 (22.8368, 24.3826) -> (22.2169, 24.5126)
  line L242 (22.2169, 24.5126) -> (21.5606, 24.5851)
  line L243 (21.5606, 24.5851) -> (20.9079, 24.6428)
  line L244 (20.9079, 24.6428) -> (20.2961, 24.7308)
  line L245 (20.2961, 24.7308) -> (19.754, 24.8898)
  line L246 (19.754, 24.8898) -> (19.2978, 25.1493)
  line L247 (19.2978, 25.1493) -> (18.929, 25.5228)
  line L248 (18.929, 25.5228) -> (18.6352, 26.0053)
  line L249 (18.6352, 26.0053) -> (18.3918, 26.5735)
  line L250 (18.3918, 26.5735) -> (18.1671, 27.1891)
  line L251 (18.1671, 27.1891) -> (17.9272, 27.8043)
  line L252 (17.9272, 27.8043) -> (17.6412, 28.3693)
  line L253 (17.6412, 28.3693) -> (17.2862, 28.8402)
  line L254 (17.2862, 28.8402) -> (16.85, 29.1851)
  line L255 (16.85, 29.1851) -> (16.3333, 29.3903)
  line L256 (16.3333, 29.3903) -> (15.748, 29.4624)
  line L257 (15.748, 29.4624) -> (15.1156, 29.4275)
  line L258 (15.1156, 29.4275) -> (14.4628, 29.3277)
  line L259 (14.4628, 29.3277) -> (13.8174, 29.2145)
  line L260 (13.8174, 29.2145) -> (13.2037, 29.1411)
  line L261 (13.2037, 29.1411) -> (12.6389, 29.1545)
  line L262 (12.6389, 29.1545) -> (12.1311, 29.2869)
  line L263 (12.1311, 29.2869) -> (11.6782, 29.5523)
  line L264 (11.6782, 29.5523) -> (11.2695, 29.9423)
  line L265 (11.2695, 29.9423) -> (10.8873, 30.4281)
  line L266 (10.8873, 30.4281) -> (10.5111, 30.9646)
  line L267 (10.5111, 30.9646) -> (10.1201, 31.4968)
  line L268 (10.1201, 31.4968) -> (9.6976, 31.9686)
  line L269 (9.6976, 31.9686) -> (9.2327, 32.3314)
  line L270 (9.2327, 32.3314) -> (8.7222, 32.5517)
  line L271 (8.7222, 32.5517) -> (8.1699, 32.6162)
  line L272 (8.1699, 32.6162) -> (7.586, 32.5344)
  line L273 (7.586, 32.5344) -> (6.9842, 32.3371)
  line L274 (6.9842, 32.3371) -> (6.3795, 32.0717)
  line L275 (6.3795, 32.0717) -> (5.7853, 31.7952)
  line L276 (5.7853, 31.7952) -> (5.2115, 31.5656)
  line L277 (5.2115, 31.5656) -> (4.6625, 31.4321)
  line L278 (4.6625, 31.4321) -> (4.1376, 31.4288)
  line L279 (4.1376, 31.4288) -> (3.6316, 31.568)
  line L280 (3.6316, 31.568) -> (3.1359, 31.8388)
  line L281 (3.1359, 31.8388) -> (2.641, 32.2092)
  line L282 (2.641, 32.2092) -> (2.1387, 32.6299)
  line L283 (2.1387, 32.6299) -> (1.6233, 33.0429)
  line L284 (1.6233, 33.0429) -> (1.0931, 33.3893)
  line L285 (1.0931, 33.3893) -> (0.5502, 33.6193)
  line L286 (0.5502, 33.6193) -> (0, 33.7)
  line L287 (0, 33.7) -> (-0.5502, 33.6193)
  line L288 (-0.5502, 33.6193) -> (-1.0931, 33.3893)
  line L289 (-1.0931, 33.3893) -> (-1.6233, 33.0429)
  line L290 (-1.6233, 33.0429) -> (-2.1387, 32.6299)
  line L291 (-2.1387, 32.6299) -> (-2.641, 32.2092)
  line L292 (-2.641, 32.2092) -> (-3.1359, 31.8388)
  line L293 (-3.1359, 31.8388) -> (-3.6316, 31.568)
  line L294 (-3.6316, 31.568) -> (-4.1376, 31.4288)
  line L295 (-4.1376, 31.4288) -> (-4.6625, 31.4321)
  line L296 (-4.6625, 31.4321) -> (-5.2115, 31.5656)
  line L297 (-5.2115, 31.5656) -> (-5.7853, 31.7952)
  line L298 (-5.7853, 31.7952) -> (-6.3795, 32.0717)
  line L299 (-6.3795, 32.0717) -> (-6.9842, 32.3371)
  line L300 (-6.9842, 32.3371) -> (-7.586, 32.5344)
  line L301 (-7.586, 32.5344) -> (-8.1699, 32.6162)
  line L302 (-8.1699, 32.6162) -> (-8.7222, 32.5517)
  line L303 (-8.7222, 32.5517) -> (-9.2327, 32.3314)
  line L304 (-9.2327, 32.3314) -> (-9.6976, 31.9686)
  line L305 (-9.6976, 31.9686) -> (-10.1201, 31.4968)
  line L306 (-10.1201, 31.4968) -> (-10.5111, 30.9646)
  line L307 (-10.5111, 30.9646) -> (-10.8873, 30.4281)
  line L308 (-10.8873, 30.4281) -> (-11.2695, 29.9423)
  line L309 (-11.2695, 29.9423) -> (-11.6782, 29.5523)
  line L310 (-11.6782, 29.5523) -> (-12.1311, 29.2869)
  line L311 (-12.1311, 29.2869) -> (-12.6389, 29.1545)
  line L312 (-12.6389, 29.1545) -> (-13.2037, 29.1411)
  line L313 (-13.2037, 29.1411) -> (-13.8174, 29.2145)
  line L314 (-13.8174, 29.2145) -> (-14.4628, 29.3277)
  line L315 (-14.4628, 29.3277) -> (-15.1156, 29.4275)
  line L316 (-15.1156, 29.4275) -> (-15.748, 29.4624)
  line L317 (-15.748, 29.4624) -> (-16.3333, 29.3903)
  line L318 (-16.3333, 29.3903) -> (-16.85, 29.1851)
  line L319 (-16.85, 29.1851) -> (-17.2862, 28.8402)
  line L320 (-17.2862, 28.8402) -> (-17.6412, 28.3693)
  line L321 (-17.6412, 28.3693) -> (-17.9272, 27.8043)
  line L322 (-17.9272, 27.8043) -> (-18.1671, 27.1891)
  line L323 (-18.1671, 27.1891) -> (-18.3918, 26.5735)
  line L324 (-18.3918, 26.5735) -> (-18.6352, 26.0053)
  line L325 (-18.6352, 26.0053) -> (-18.929, 25.5228)
  line L326 (-18.929, 25.5228) -> (-19.2978, 25.1493)
  line L327 (-19.2978, 25.1493) -> (-19.754, 24.8898)
  line L328 (-19.754, 24.8898) -> (-20.2961, 24.7308)
  line L329 (-20.2961, 24.7308) -> (-20.9079, 24.6428)
  line L330 (-20.9079, 24.6428) -> (-21.5606, 24.5851)
  line L331 (-21.5606, 24.5851) -> (-22.2169, 24.5126)
  line L332 (-22.2169, 24.5126) -> (-22.8368, 24.3826)
  line L333 (-22.8368, 24.3826) -> (-23.3835, 24.1615)
  line L334 (-23.3835, 24.1615) -> (-23.8295, 23.8295)
  line L335 (-23.8295, 23.8295) -> (-24.1615, 23.3835)
  line L336 (-24.1615, 23.3835) -> (-24.3826, 22.8368)
  line L337 (-24.3826, 22.8368) -> (-24.5126, 22.2169)
  line L338 (-24.5126, 22.2169) -> (-24.5851, 21.5606)
  line L339 (-24.5851, 21.5606) -> (-24.6428, 20.9079)
  line L340 (-24.6428, 20.9079) -> (-24.7308, 20.2961)
  line L341 (-24.7308, 20.2961) -> (-24.8898, 19.754)
  line L342 (-24.8898, 19.754) -> (-25.1493, 19.2978)
  line L343 (-25.1493, 19.2978) -> (-25.5228, 18.929)
  line L344 (-25.5228, 18.929) -> (-26.0053, 18.6352)
  line L345 (-26.0053, 18.6352) -> (-26.5735, 18.3918)
  line L346 (-26.5735, 18.3918) -> (-27.1891, 18.1671)
  line L347 (-27.1891, 18.1671) -> (-27.8043, 17.9272)
  line L348 (-27.8043, 17.9272) -> (-28.3693, 17.6412)
  line L349 (-28.3693, 17.6412) -> (-28.8402, 17.2862)
  line L350 (-28.8402, 17.2862) -> (-29.1851, 16.85)
  line L351 (-29.1851, 16.85) -> (-29.3903, 16.3333)
  line L352 (-29.3903, 16.3333) -> (-29.4624, 15.748)
  line L353 (-29.4624, 15.748) -> (-29.4275, 15.1156)
  line L354 (-29.4275, 15.1156) -> (-29.3277, 14.4628)
  line L355 (-29.3277, 14.4628) -> (-29.2145, 13.8174)
  line L356 (-29.2145, 13.8174) -> (-29.1411, 13.2037)
  line L357 (-29.1411, 13.2037) -> (-29.1545, 12.6389)
  line L358 (-29.1545, 12.6389) -> (-29.2869, 12.1311)
  line L359 (-29.2869, 12.1311) -> (-29.5523, 11.6782)
  line L360 (-29.5523, 11.6782) -> (-29.9423, 11.2695)
  line L361 (-29.9423, 11.2695) -> (-30.4281, 10.8873)
  line L362 (-30.4281, 10.8873) -> (-30.9646, 10.5111)
  line L363 (-30.9646, 10.5111) -> (-31.4968, 10.1201)
  line L364 (-31.4968, 10.1201) -> (-31.9686, 9.6976)
  line L365 (-31.9686, 9.6976) -> (-32.3314, 9.2327)
  line L366 (-32.3314, 9.2327) -> (-32.5517, 8.7222)
  line L367 (-32.5517, 8.7222) -> (-32.6162, 8.1699)
  line L368 (-32.6162, 8.1699) -> (-32.5344, 7.586)
  line L369 (-32.5344, 7.586) -> (-32.3371, 6.9842)
  line L370 (-32.3371, 6.9842) -> (-32.0717, 6.3795)
  line L371 (-32.0717, 6.3795) -> (-31.7952, 5.7853)
  line L372 (-31.7952, 5.7853) -> (-31.5656, 5.2115)
  line L373 (-31.5656, 5.2115) -> (-31.4321, 4.6625)
  line L374 (-31.4321, 4.6625) -> (-31.4288, 4.1376)
  line L375 (-31.4288, 4.1376) -> (-31.568, 3.6316)
  line L376 (-31.568, 3.6316) -> (-31.8388, 3.1359)
  line L377 (-31.8388, 3.1359) -> (-32.2092, 2.641)
  line L378 (-32.2092, 2.641) -> (-32.6299, 2.1387)
  line L379 (-32.6299, 2.1387) -> (-33.0429, 1.6233)
  line L380 (-33.0429, 1.6233) -> (-33.3893, 1.0931)
  line L381 (-33.3893, 1.0931) -> (-33.6193, 0.5502)
  line L382 (-33.6193, 0.5502) -> (-33.7, 0)
  line L383 (-33.7, 0) -> (-33.6193, -0.5502)
extrude "可换压片基体 (1)" add sketch "草图1 (3)" along normal blind 6 separate body makes body 3 in component "03_可换镜像凹纹压片"
ref_plane "工作平面1" through (0, 0, -12) normal (0, 0, 1) x (1, 0, 0) in component "03_可换镜像凹纹压片"
sketch "草图2 (3)" plane through (0, 0, -12) normal (0, 0, 1) x (1, 0, 0) in component "03_可换镜像凹纹压片"
  circle A0 centre (0, 0) radius 8
extrude "压片背面螺纹座 (1)" add sketch "草图2 (3)" along normal blind 12.03 bodies 3 in component "03_可换镜像凹纹压片"
ref_plane "工作平面2" through (0, 0, -12.03) normal (0, 0, 1) x (1, 0, 0) in component "03_可换镜像凹纹压片"
sketch "草图3 (3)" plane through (0, 0, -12.03) normal (0, 0, 1) x (1, 0, 0) in component "03_可换镜像凹纹压片"
  circle A0 centre (0, 0) radius 3.375
extrude "M8 盲孔 (1)" cut sketch "草图3 (3)" along normal blind 11.03 bodies 3 in component "03_可换镜像凹纹压片"
thread "M8x1.25 内螺纹" "ISO Metric profile 8.0 M8x1.25 M8x1.25 6H" major diameter 8.17 minor diameter 6.7795 pitch 1.25 angle 60 modelled right hand crest width 0.343 on face at (3.3582, 0.336, -8.3333) crest through (3.3898, 0, -11.6875) on bodies 3 in component "03_可换镜像凹纹压片"
ref_plane "工作平面3" through (0, 0, 4.8) normal (0, 0, 1) x (1, 0, 0) in component "03_可换镜像凹纹压片"